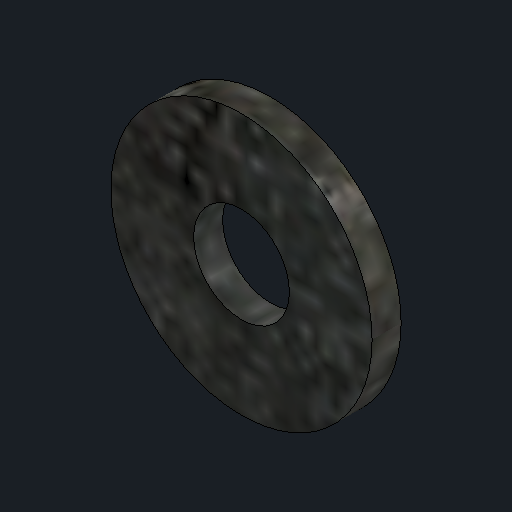
# Autodesk Inventor part: M6-18x2-Hardened-Washer
Saved by Autodesk Inventor 2027.1 (Build 311270010, 270A)
## iProperties
Created: 2026-11-15
Part Number: M6-18x2-Hardened-Washer
Material: Steel
Description: Hardened steel load-spreading washer
Document SubType Name: Modeling
Designer: queezz
Density: 7.85 g/cm^3
Appearance: Plate
Author: queezz
Autodesk Inventor part; units mm, degrees
ref_plane "YZ Plane" through (0, 0, 0) normal (1, 0, 0) x (0, 1, 0)
ref_plane "XZ Plane" through (0, 0, 0) normal (0, 1, 0) x (-1, 0, 0)
ref_plane "XY Plane" through (0, 0, 0) normal (0, 0, 1) x (1, 0, 0)
sketch "Sketch1" plane through (0, 0, 0) normal (0, 0, 1) x (1, 0, 0)
  circle A0 centre (0, 0) radius 3.3
  circle A1 centre (0, 0) radius 9
  dimension "d0" = 2
  constraints: 2 centre point
extrude "Hardened washer envelope" add sketch "Sketch1" against normal blind 2
body "Solid1"
